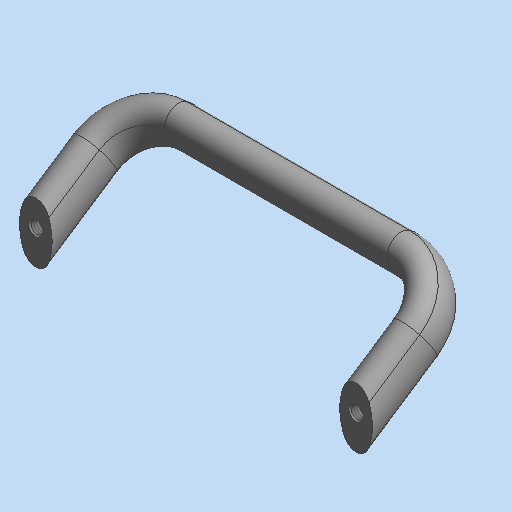
# Autodesk Inventor part: MM0861AN200_G22_317
Saved by Autodesk Inventor 2023.3 (Build 273359000, 359)
## iProperties
Part Number: MM0861AN200_G22_317
Material: Allgemein
Catalog Web Link: www.cadenas.de
Description: GN 565.2 A-Inclined cabinet „U“ handles, Type A, Mounting from the back (threaded blind bore)
Vendor: GANTER
Document SubType Name: Modeling
Designer: partserver
Manufacturer: GANTER
Mass: 112 g
Surface Area: 118.613 cm^2
Volume: 43.0027 cm^3
Density: 1 g/cm^3
Appearance: PSOLRGB-191-191-191
Category: PARTsolutions
Company: GANTER
PSOL_IDENT_0: {$CADENAS_DATA\23d-libs\ganter\data\1_2\gn_565_2\gn565_2.prj},242 {VTYP=3D},{NB=Inclined cabinet „U“
PSOL_IDENT_1: handle GN 565.2-20-128-A-SR},{LINA=Inclined cabinet „U“ handle GN 565.2-20-128-A-SR},{NN=GN 565.2 A
PSOL_IDENT_2: },{DATE=24.10.2020 12:08:40},{GEOMDATE=19.10.2020 11:26:32},{VERSION=v1},{LINEID=80},{WBVAR=},{WBNUM
PSOL_IDENT_3: ERIC=}  {NB=Schraeger Buegelgriff GN 565.2-20-128-A-SR},{LINA=Schraeger Buegelgriff GN 565.2-20-128-
PSOL_IDENT_4: A-SR},{KT=DUMMY},{PARTNUMBER=GN 565.2-20-128-A-SR},{NORMNR=GN 565.2},{AUSWAHL=SW,BL,EL},{B1=20},{L=1
PSOL_IDENT_5: 28},{A=13},{B2=24},{B3=32},{B4=50},{B5=13.5},{D1=M6},{D=6},{H1=32},{H2=48},{H3=50},{H4=13.5},{R=13},
PSOL_IDENT_6: {T=10},{OFLVIS=silber (SR)},{KDM=4.917},{F1=0.75},{F2=0.75},{F3=0.75},{OFL=SR},{WEIGHT=0.1120},{CTN=
PSOL_IDENT_7: 83024900},{ROHS=YES},{INFOGANTER=Produktdetails},{INFOGANTERX=https://www.ganternorm.com/de/produkte
PSOL_IDENT_8: /1.2-Bedienen-mit-Maschinen-und-Geraetegriffen/GN-565.2-Schraege-Buegelgriffe-Aluminium},{DIST=2.933
PSOL_IDENT_9: 333}
NB: Inclined cabinet „U“ handle GN 565.2-20-128-A-SR
NN: GN 565.2 A
NT: Inclined cabinet „U“ handles, Type A, Mounting from the back (threaded blind bore)
NBSYN: Inclined cabinet „U“ handle $PARTNUMBER.
LINA: Inclined cabinet „U“ handle GN 565.2-20-128-A-SR
CATALOG: Ganter
PARTNUMBER: GN 565.2-20-128-A-SR
B1: 20
L: 128
A: 13
B2: 24
B3: 32
B4: 50
B5: 13.5
D1: M6
H1: 32
H2: 48
R: 13
T: 10
OFLVIS: silver (SR)
WEIGHT: 0.112
CTN: 83024900
ROHS: YES
INFOGANTER: Product details
SUPPLIER: GANTER
ARTICLENO: Inclined cabinet „U“ handle GN 565.2-20-128-A-SR
BOMINFO: Inclined cabinet „U“ handle GN 565.2-20-128-A-SR
CREATOR: CADENAS GmbH
MaxAbmaße: 47,789 x 48,002 x 141 (FM)
RBPARTMADEOF: GN 565.2-20-128-A-SR
Title: Inclined cabinet „U“ handle GN 565.2-20-128-A-SR
Author: Cadenas PARTsolutions
Comments: Inclined cabinet „U“ handles, Type A, Mounting from the back (threaded blind bore)
Keywords: =<RBPARTMADEOF>
Revision Number: 01
Autodesk Inventor part; units mm, degrees
ref_plane "YZ Plane" through (0, 0, 0) normal (1, 0, 0) x (0, 1, 0)
ref_plane "XZ Plane" through (0, 0, 0) normal (0, 1, 0) x (-1, 0, 0)
ref_plane "XY Plane" through (0, 0, 0) normal (0, 0, 1) x (1, 0, 0)
sketch "Skizze_1" plane through (0, 0, 0) normal (1, 0, 0) x (0, 1, 0)
  arc A0 (47.8592, -22.5564) -> (39.2282, -16.8312) centre (42.4728, -21.3082) ccw
  arc A1 (39.2282, -16.8312) -> (32.1437, -27.5116) centre (48.0843, -30.3955) ccw
  arc A2 (32.1437, -27.5116) -> (40.7747, -33.2367) centre (37.5301, -28.7597) ccw
  arc A3 (40.7747, -33.2367) -> (47.8592, -22.5564) centre (31.9187, -19.6724) ccw
  constraints: 8 point on circle, 4 centre point
extrude "Extrusion1" add sketch "Skizze_1" along normal mid plane 89
sketch "Skizze_2" plane through (44.5, 0, 0) normal (1, 0, 0) x (0, 0, -1)
  line L0 (22.5883, 18.2238) -> (5.9216, 29.2792)
  arc A0 (22.5564, 47.8592) -> (16.8312, 39.2282) centre (21.3082, 42.4728) ccw
  arc A1 (16.8312, 39.2282) -> (27.5116, 32.1437) centre (30.3955, 48.0843) ccw
  arc A2 (27.5116, 32.1437) -> (33.2367, 40.7747) centre (28.7597, 37.5301) ccw
  arc A3 (33.2367, 40.7747) -> (22.5564, 47.8592) centre (19.6724, 31.9187) ccw
  constraints: 8 point on circle, 4 centre point, 2 end point
revolve "Revolution1" add sketch "Skizze_2" angle 90 about axis through (44.5, 18.2238, -22.5883) along (0, -0.5527708, -0.8333333)
sketch "Sketch_3" plane through (-44.5, 0, 0) normal (1, 0, 0) x (0, 0, -1)
  line L0 (22.5883, 18.2238) -> (5.9216, 29.2792)
  arc A0 (22.5564, 47.8592) -> (16.8312, 39.2282) centre (21.3082, 42.4728) ccw
  arc A1 (16.8312, 39.2282) -> (27.5116, 32.1437) centre (30.3955, 48.0843) ccw
  arc A2 (27.5116, 32.1437) -> (33.2367, 40.7747) centre (28.7597, 37.5301) ccw
  arc A3 (33.2367, 40.7747) -> (22.5564, 47.8592) centre (19.6724, 31.9187) ccw
  constraints: 8 point on circle, 4 centre point, 2 end point
revolve "Revolution2" add sketch "Sketch_3" angle 90 about axis through (-44.5, 18.2238, -22.5883) along (0, 0.5527708, 0.8333333)
sketch "Sketch_1" plane through (0, 29.2792, -5.9216) normal (0, 0.8333333, -0.5527708) x (1, 0, 0)
  arc A0 (58.8214, 16.4082) -> (58.8214, 3.5918) centre (73.6994, 10) ccw
  arc A1 (58.8214, 3.5918) -> (69.1786, 3.5918) centre (64, 5.5291) ccw
  arc A2 (69.1786, 3.5918) -> (69.1786, 16.4082) centre (54.3006, 10) ccw
  arc A3 (69.1786, 16.4082) -> (58.8214, 16.4082) centre (64, 14.4709) ccw
  constraints: 8 point on circle, 4 centre point
extrude "Extrusion2" add sketch "Sketch_1" against normal blind 48
sketch "Sketch_2" plane through (0, 29.2792, -5.9216) normal (0, 0.8333333, -0.5527708) x (1, 0, 0)
  arc A0 (-69.1786, 16.4082) -> (-69.1786, 3.5918) centre (-54.3006, 10) ccw
  arc A1 (-69.1786, 3.5918) -> (-58.8214, 3.5918) centre (-64, 5.5291) ccw
  arc A2 (-58.8214, 3.5918) -> (-58.8214, 16.4082) centre (-73.6994, 10) ccw
  arc A3 (-58.8214, 16.4082) -> (-69.1786, 16.4082) centre (-64, 14.4709) ccw
  constraints: 8 point on circle, 4 centre point
extrude "Extrusion3" add sketch "Sketch_2" against normal blind 48
sketch "Sketch_8" plane through (0, 0, 0) normal (1, 0, 0) x (0, 1, 0)
  line L0 (-50, 50) -> (-50, -50)
  line L1 (-50, -50) -> (0, -50)
  line L2 (0, -50) -> (0, 50)
  line L3 (0, 50) -> (-50, 50)
  constraints: 8 end point
extrude "Extrusion4" cut sketch "Sketch_8" along normal mid plane 167
sketch "Sketch7" plane through (73.6994, 0, 1.5) normal (0, -1, 0) x (1, 0, 0)
  point P0 (-9.6994, -1.5)
hole "Hole1" at (64, 0, 0) direction (0, 1, 0) diameter 4.917 depth 11 tip angle 120 countersink diameter 6 countersink angle 90 thread size "M6x1" class "6H" standard "ISO Metric profile"
sketch "Sketch8" plane through (-54.3006, 0, 1.5) normal (0, -1, 0) x (1, 0, 0)
  point P0 (-9.6994, -1.5)
hole "Hole2" at (-64, 0, 0) direction (0, 1, 0) diameter 4.917 depth 11 tip angle 120 countersink diameter 6 countersink angle 90 thread size "M6x1" class "6H" standard "ISO Metric profile"
body "Solid1"
